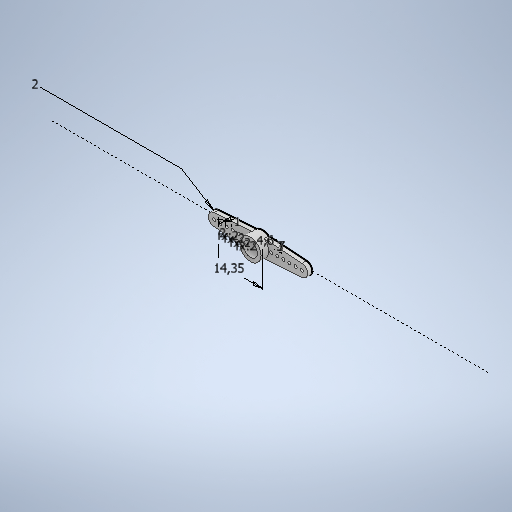
# Autodesk Inventor part: sg92r arm
Saved by Autodesk Inventor 2025.3 (Build 293356000, 356)
## iProperties
Created: 2025-09-24
Part Number: sg92r arm
Material: Generic
Document SubType Name: Modeling
Designer: kuusela
Density: 1 g/cm^3
Appearance: Default
Author: kuusela
Autodesk Inventor part; units mm, degrees
ref_plane "YZ Plane" through (0, 0, 0) normal (1, 0, 0) x (0, 1, 0)
ref_plane "XZ Plane" through (0, 0, 0) normal (0, 1, 0) x (-1, 0, 0)
ref_plane "XY Plane" through (0, 0, 0) normal (0, 0, 1) x (1, 0, 0)
sketch "Sketch1" plane through (0, 0, 0) normal (0, 0, 1) x (1, 0, 0)
  circle A0 centre (0, 0) radius 2.3
  line L0 (0, 0) -> (74.5423, 0) construction
  line L1 (0, 0) -> (-69.4527, 0) construction
  circle A1 centre (-12.35, 0) radius 0.5
  circle A2 centre (-10.35, 0) radius 0.5
  circle A3 centre (-14.35, 0) radius 0.5
  line L2 (0, 0) -> (0, 3) construction
  line L3 (0, 3) -> (-14.4884, 1.9952)
  arc A4 (-14.4884, 1.9952) -> (-14.4884, -1.9952) centre (-14.35, 0) ccw
  line L4 (-14.4884, -1.9952) -> (0, -3)
  line L5 (0, -3) -> (0, 0) construction
  circle A5 centre (12.35, 0) radius 0.5
  circle A6 centre (10.35, 0) radius 0.5
  circle A7 centre (14.35, 0) radius 0.5
  line L6 (0, 3) -> (14.4884, 1.9952)
  arc A8 (14.4884, -1.9952) -> (14.4884, 1.9952) centre (14.35, 0) ccw
  line L7 (14.4884, -1.9952) -> (0, -3)
  circle A9 centre (0, 0) radius 3.5
  circle A10 centre (-8.35, 0) radius 0.5
  circle A11 centre (-6.35, 0) radius 0.5
  circle A12 centre (-4.35, 0) radius 0.5
  circle A13 centre (8.35, 0) radius 0.5
  circle A14 centre (6.35, 0) radius 0.5
  circle A15 centre (4.35, 0) radius 0.5
  point P0 (-2.0174, -2.8601)
  point P1 (-2.0174, 2.8601)
  point P2 (2.0174, 2.8601)
  point P3 (2.0174, -2.8601)
  dimension "d0" = 4.6
  dimension "d2" = 1
  dimension "d8" = 14.35
  dimension "d9" = 3
  dimension "d10" = 2
  dimension "d13" = 7
  dimension "d19" = 2
  dimension "d20" = 2
  dimension "d21" = 2
  dimension "d22" = 2
  dimension "d23" = 2
  constraints: 16 centre point, 16 end point, 9 symmetric about line, 6 point on line, 5 equal radius, 4 coincident, 4 point on circle, 2 horizontal, 2 tangent, 2 vertical, 1 collinear, 7 other
  measures "d0" diameter of A0
  measures "d2" diameter of A1
  measures "d8" distance of point (0, 0) A3.centre
  measures "d9" distance of L2.end point (0, 0)
  measures "d10" radius of A4
  measures "d13" diameter of A9
  measures "d19" distance of A1.centre A3.centre
  measures "d20" distance of A2.centre A1.centre
  measures "d21" distance of A10.centre A2.centre
  measures "d22" distance of A11.centre A10.centre
  measures "d23" distance of A12.centre A11.centre
extrude "Extrusion1" add sketch "Sketch1" along normal blind 4 contours L6 A9 L7 L4 L3 | L3 A9 L6 | L4 L7 A9
extrude "Extrusion2" add sketch "Sketch1" along normal blind 1.5 contours A9 L4 A4 L3 | L6 A8 L7 A9
equation "\"d20\" = d19"
equation "\"d21\" = d20"
equation "\"d22\" = d21"
equation "\"d23\" = d22"
body "Solid1"
